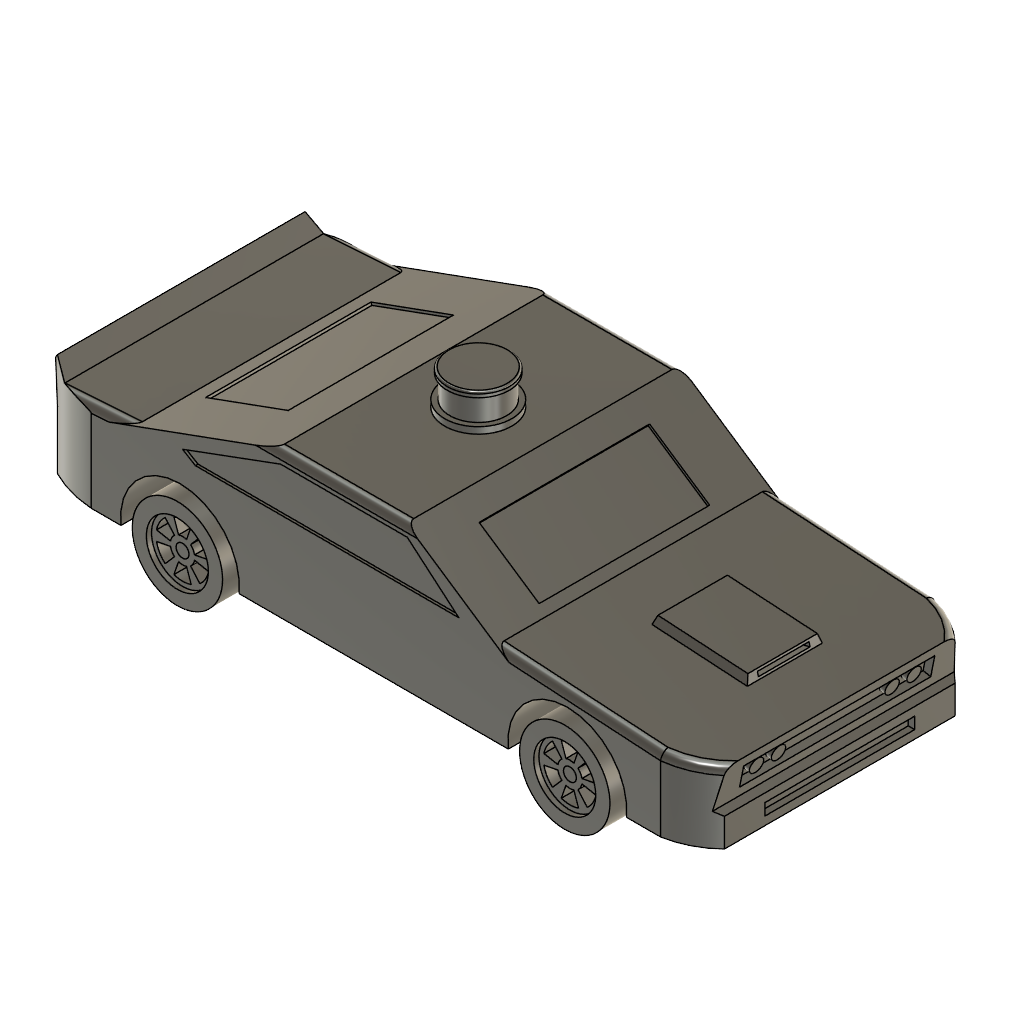
Ackermann_Challenger (Autodesk Fusion 360 design; units mm, degrees)
part number: 2026-11-21-11-42-55-945
part number: 2026-11-21-13-18-45-082
part number: 2026-11-21-13-18-45-097
part number: 2026-11-21-13-18-45-101
part number: 2026-11-21-13-18-45-105
part number: 2026-11-21-13-18-45-110
part number: 2026-11-21-13-18-45-114
part number: 2026-11-21-13-18-45-119
part number: 2026-11-21-13-18-45-123
part number: 2026-11-21-13-18-45-128
part number: 2026-11-21-15-02-55-221
part number: 2026-11-21-15-02-55-302
part number: 2026-11-21-15-02-55-381
part number: 2026-11-21-15-02-55-462
part number: 2026-11-21-15-02-55-542
part number: 2026-11-21-15-02-55-624
part number: 2026-11-21-15-02-55-705
part number: 2026-11-21-15-02-55-805
part number: 2026-11-21-15-02-55-884
Autodesk Fusion 360 part; units mm, degrees
sketch "Boceto1" plane through (0, 0, 0) normal (0, 0, 1) x (1, 0, 0)
  line L0 (245, -50) -> (-245, -50)
  line L1 (-245, -50) -> (-245, 50)
  line L2 (-245, 50) -> (245, 50)
  line L3 (245, 50) -> (245, -50)
  line L4 (245, -50) -> (-245, 50) construction
  line L5 (-245, -50) -> (245, 50) construction
  line L6 (0, 0) -> (150, 0) construction
  line L7 (163, -60) -> (137, -60)
  line L8 (137, -60) -> (137, 60)
  line L9 (137, 60) -> (163, 60)
  line L10 (163, 60) -> (163, -60)
  line L11 (163, -60) -> (137, 60) construction
  line L12 (137, -60) -> (163, 60) construction
  line L13 (0, 0) -> (-150, 0) construction
  line L14 (-137, 60) -> (-163, 60)
  line L15 (-163, 60) -> (-163, -60)
  line L16 (-163, -60) -> (-137, -60)
  line L17 (-137, -60) -> (-137, 60)
  line L18 (-137, 60) -> (-163, -60) construction
  line L19 (-163, 60) -> (-137, -60) construction
  circle A0 centre (150, -60) radius 4
  circle A1 centre (150, 60) radius 4
  line L20 (137, 68) -> (163, 68)
  line L21 (163, 68) -> (163, -68)
  line L22 (163, -68) -> (137, -68)
  line L23 (137, -68) -> (137, 68)
  line L24 (137, 68) -> (163, -68) construction
  line L25 (163, 68) -> (137, -68) construction
  point P0 (150, 0)
  point P1 (-150, 0)
  point P2 (150, 0)
  dimension "d1" = 490
  dimension "d2" = 100
  dimension "d3" = 150
  dimension "d4" = 26
  dimension "d5" = 120
  dimension "d6" = 150
  dimension "d7" = 26
  dimension "d8" = 120
  dimension "d13" = 8
  dimension "d14" = 8
  dimension "d23" = 10
  dimension "d24" = 10
  dimension "d25" = 136
  constraint horizontal L0
  constraint perpendicular L0 L1
  constraint parallel L0 L2
  constraint parallel L1 L3
  constraint coincident L4 L6.start
  constraint coincident L5 L6.start
  constraint coincident L6.start L13.start
  constraint horizontal L6
  constraint horizontal L7
  constraint perpendicular L7 L8
  constraint parallel L7 L9
  constraint parallel L8 L10
  constraint coincident L11 P2
  constraint coincident L12 P2
  constraint coincident P2 P0
  constraint parallel L6 L13
  constraint horizontal L14
  constraint perpendicular L14 L15
  constraint parallel L14 L16
  constraint parallel L15 L17
  constraint coincident L18 P1
  constraint coincident L19 P1
  constraint coincident P1 L13.end
  constraint midpoint L7 A0.centre
  constraint midpoint L9 A1.centre
  constraint horizontal L20
  constraint perpendicular L20 L21
  constraint parallel L20 L22
  constraint parallel L21 L23
  constraint coincident L24 P2
  constraint coincident L25 P2
  measures "d1" distance of L1.end L2.end
  measures "d2" distance of L0.end L1.end
  measures "d3" distance of L6.start P2
  measures "d4" distance of L8.end L9.end
  measures "d5" distance of L7.end L8.end
  measures "d6" distance of L6.start P1
  measures "d7" distance of L15.end L16.end
  measures "d8" distance of L14.end L15.end
  measures "d13" diameter of A0
  measures "d14" diameter of A1
  measures "d23" distance of L0 A0.centre
  measures "d24" distance of L2 A1.centre
  measures "d25" distance of L20.end L21.end
extrude "Extruir1" add sketch "Boceto1" along normal blind 10 contours L0 L2 L3 L10 L21 | L0 L7 L8 L10 A0 L21 L23 | L0 L2 L8 L10 L21 L23 | L0 L2 L8 L17 L23 | L2 L8 L9 L10 A1 L21 L23 | L7 A0 L21 L22 L23 | L0 L15 L16 L17 | L0 L2 L15 L17 | L9 A1 L20 L21 L23 | L0 L1 L2 L15 | L2 L14 L15 L17 makes body 1
sketch "Boceto2" plane through (0, -60, 0) normal (0, -1, 0) x (1, 0, 0)
  line L0 (-163, 0) -> (-137, 0)
  line L1 (-137, 0) -> (-137, 10)
  line L2 (-137, 10) -> (-163, 10)
  line L3 (-163, 10) -> (-163, 0)
  line L4 (0, 10) -> (-150, 10) construction
  line L5 (-150, 10) -> (-150, 5) construction
  circle A0 centre (-150, 5) radius 5
  dimension "d17" = 150
  dimension "d18" = 10
  constraint perpendicular L1 L4
  constraint perpendicular L4 L5
  constraint coincident L5.end A0.centre
  measures "d17" distance of L4.start L4.end
  measures "d18" diameter of A0
extrude "Extruir2" add sketch "Boceto2" along normal blind 25 contours A0 bodies 1
mirror "Simetría1" about plane through (0, 0, 0) normal (0, 1, 0) of "Extruir2"
extrude "Extruir3" add sketch "Boceto1" along normal blind 16 from surface at -3 separate body contours L7 A0 | L7 A0 | L9 A1 | L9 A1 makes body 2 at (153.1885, -57.5848, 2.3333) makes body 3 at (147.2071, 57.1365, 7.6667)
ref_plane "PlanoDeObra1" through (0, 0, 10.5) normal (0, 0, 1) x (1, 0, 0)
sketch "Boceto3" plane through (0, 0, 10.5) normal (0, 0, 1) x (1, 0, 0)
  line L0 (144, 54) -> (156, 54)
  line L1 (156, 54) -> (156, 81)
  line L2 (156, 81) -> (144, 81)
  line L3 (144, 81) -> (144, 54)
extrude "Extruir4" add sketch "Boceto3" along normal blind 4 bodies 3
ref_plane "PlanoDeObra2" through (0, 0, -0.5) normal (0, 0, 1) x (1, 0, 0)
sketch "Boceto4" plane through (0, 0, -0.5) normal (0, 0, 1) x (1, 0, 0)
  line L0 (144, 54) -> (156, 54)
  line L1 (156, 54) -> (156, 81)
  line L2 (156, 81) -> (144, 81)
  line L3 (144, 81) -> (144, 54)
extrude "Extruir5" add sketch "Boceto4" against normal blind 4 bodies 3
sketch "Boceto5" plane through (0, 0, -0.5) normal (0, 0, 1) x (1, 0, 0)
  line L0 (144, 76) -> (156, 76)
  line L1 (156, 76) -> (156, 81)
  line L2 (156, 81) -> (144, 81)
  line L3 (144, 81) -> (144, 76)
extrude "Extruir6" add sketch "Boceto5" along normal blind 11 bodies 3
ref_plane "PlanoDeObra3" through (0, 0, 10.5) normal (0, 0, 1) x (1, 0, 0)
sketch "Boceto7" plane through (0, 0, 10.5) normal (0, 0, 1) x (1, 0, 0)
  line L0 (144, -54) -> (156, -54)
  line L1 (156, -54) -> (156, -81)
  line L2 (156, -81) -> (144, -81)
  line L3 (144, -81) -> (144, -54)
extrude "Extruir8" add sketch "Boceto7" along normal blind 4 bodies 2
ref_plane "PlanoDeObra4" through (0, 0, -0.5) normal (0, 0, 1) x (1, 0, 0)
sketch "Boceto8" plane through (0, 0, -0.5) normal (0, 0, 1) x (1, 0, 0)
  line L0 (144, -54) -> (156, -54)
  line L1 (156, -54) -> (156, -81)
  line L2 (156, -81) -> (144, -81)
  line L3 (144, -81) -> (144, -54)
extrude "Extruir9" add sketch "Boceto8" against normal blind 4 bodies 2
sketch "Boceto9" plane through (0, 0, -0.5) normal (0, 0, 1) x (1, 0, 0)
  line L0 (144, -76) -> (156, -76)
  line L1 (156, -76) -> (156, -81)
  line L2 (156, -81) -> (144, -81)
  line L3 (144, -81) -> (144, -76)
extrude "Extruir10" add sketch "Boceto9" along normal blind 11 bodies 2
sketch "Boceto11" plane through (0, 81, 0) normal (0, 1, 0) x (1, 0, 0)
  line L0 (156, -14.5) -> (156, 4.5)
  line L1 (156, 4.5) -> (144, 4.5)
  line L2 (144, 4.5) -> (144, -14.5)
  line L3 (144, -14.5) -> (156, -14.5)
  circle A0 centre (150, -5) radius 5
extrude "Extruir12" add sketch "Boceto11" along normal blind 22 contours A0 bodies 3
sketch "Boceto12" plane through (0, -81, 0) normal (0, -1, 0) x (-1, 0, 0)
  line L0 (-144, -14.5) -> (-144, 4.5)
  line L1 (-144, 4.5) -> (-156, 4.5)
  line L2 (-156, 4.5) -> (-156, -14.5)
  line L3 (-156, -14.5) -> (-144, -14.5)
  circle A0 centre (-150, -5) radius 5
extrude "Extruir13" add sketch "Boceto12" along normal blind 22 contours A0 bodies 2
extrude "Extruir14" add 1 faces at (-148.7042, -85, 3.3751) along direction (0, -1, 0) blind 18 on bodies 1 bodies 1
extrude "Extruir15" add 1 faces at (-149.3911, 85, 2.9517) along direction (0, 1, 0) blind 18 on bodies 1 bodies 1
sketch "Boceto13" plane through (0, -103, 0) normal (0, -1, 0) x (1, 0, 0)
  circle A0 centre (150, 5) radius 5
  circle A1 centre (150, 5) radius 35
  circle A2 centre (150, 5) radius 24
  circle A3 centre (150, 5) radius 5
  dimension "d61" = 70
  dimension "d62" = 48
  dimension "d63" = 10
  constraint concentric A0 A1
  constraint concentric A1 A2
  constraint concentric A2 A3
  measures "d61" diameter of A1
  measures "d62" diameter of A2
  measures "d63" diameter of A3
extrude "Extruir17" add sketch "Boceto13" along normal blind 5 and the other way blind 21 separate body contours A1 makes body 4
extrude "Extruir18" add sketch "Boceto13" along normal blind 1 and the other way blind 17 separate body contours A2 makes body 5
combine "Combinar1" operation add target body 4 tool bodies 5
sketch "Boceto14" plane through (0, -104, 0) normal (0, -1, 0) x (1, 0, 0)
  circle A0 centre (150, 5) radius 5
  circle A1 centre (150, 5) radius 24
  arc A2 (153.0929, 13.9824) -> (146.9071, 13.9824) centre (150, 5) ccw
  arc A3 (156.6741, 24.3831) -> (143.3259, 24.3831) centre (150, 5) ccw
  line L0 (153.0929, 13.9824) -> (156.6741, 24.3831)
  line L1 (146.9071, 13.9824) -> (143.3259, 24.3831)
  arc A4 (143.7674, 12.1697) -> (140.6745, 6.8127) centre (150, 5) ccw
  arc A5 (136.5508, 20.4715) -> (129.8766, 8.9116) centre (150, 5) ccw
  line L2 (143.7674, 12.1697) -> (136.5508, 20.4715)
  line L3 (140.6745, 6.8127) -> (129.8766, 8.9116)
  arc A6 (140.6745, 3.1873) -> (143.7674, -2.1697) centre (150, 5) ccw
  arc A7 (129.8766, 1.0884) -> (136.5508, -10.4715) centre (150, 5) ccw
  line L4 (140.6745, 3.1873) -> (129.8766, 1.0884)
  line L5 (143.7674, -2.1697) -> (136.5508, -10.4715)
  arc A8 (146.9071, -3.9824) -> (153.0929, -3.9824) centre (150, 5) ccw
  arc A9 (143.3259, -14.3831) -> (156.6741, -14.3831) centre (150, 5) ccw
  line L6 (146.9071, -3.9824) -> (143.3259, -14.3831)
  line L7 (153.0929, -3.9824) -> (156.6741, -14.3831)
  arc A10 (156.2326, -2.1697) -> (159.3255, 3.1873) centre (150, 5) ccw
  arc A11 (163.4492, -10.4715) -> (170.1234, 1.0884) centre (150, 5) ccw
  line L8 (156.2326, -2.1697) -> (163.4492, -10.4715)
  line L9 (159.3255, 3.1873) -> (170.1234, 1.0884)
  arc A12 (159.3255, 6.8127) -> (156.2326, 12.1697) centre (150, 5) ccw
  arc A13 (170.1234, 8.9116) -> (163.4492, 20.4715) centre (150, 5) ccw
  line L10 (159.3255, 6.8127) -> (170.1234, 8.9116)
  line L11 (156.2326, 12.1697) -> (163.4492, 20.4715)
extrude "Extruir19" cut sketch "Boceto14" against normal blind 18 contours A2 A3 L0 L1 | A4 A5 L2 L3 | A6 A7 L4 L5 | A8 A9 L6 L7 | A10 A11 L8 L9 | A12 A13 L10 L11 bodies 4
mirror "Simetría2" about plane through (0, 0, 0) normal (0, 1, 0) of bodies 4 makes body 6
mirror "Simetría3" about plane through (0, 0, 0) normal (1, 0, 0) of bodies 6 4 makes body 7 at (-184.9565, -89, 3.2554) makes body 8 at (-184.9565, 89, 3.2554)
sketch "Boceto15" plane through (0, 0, 0) normal (0, 1, 0) x (1, 0, 0)
  line L0 (-255, 0) -> (255, 0)
  line L1 (255, 0) -> (255, -22)
  line L2 (255, -22) -> (250, -25)
  line L3 (250, -25) -> (256, -55)
  line L4 (256, -55) -> (95, -65)
  line L5 (95, -65) -> (25, -112)
  line L6 (25, -112) -> (-75, -112)
  line L7 (-75, -112) -> (-185, -72)
  line L8 (-185, -72) -> (-245, -68)
  line L9 (-245, -68) -> (-255, -80)
  line L10 (-255, -80) -> (-258, -76)
  line L11 (-258, -76) -> (-255, -45)
  line L12 (-255, -45) -> (-255, 0)
extrude "Extruir20" add sketch "Boceto15" along normal mid plane 212 separate body makes body 9
sketch "Boceto16" plane through (0, -106, 0) normal (0, -1, 0) x (1, 0, 0)
  line L0 (-258, 76) -> (-255, 45)
  line L1 (-255, 45) -> (-255, 0)
  line L2 (-255, 0) -> (255, 0)
  line L3 (255, 0) -> (255, 22)
  line L4 (255, 22) -> (250, 25)
  line L5 (250, 25) -> (256, 55)
  line L6 (256, 55) -> (95, 65)
  line L7 (95, 65) -> (25, 112)
  line L8 (25, 112) -> (-75, 112)
  line L9 (-75, 112) -> (-185, 72)
  line L10 (-185, 72) -> (-245, 68)
  line L11 (-245, 68) -> (-255, 80)
  line L12 (-255, 80) -> (-258, 76)
  line L13 (0, 0) -> (150, 0) construction
  line L14 (0, 0) -> (-150, 0) construction
  line L15 (-150, 0) -> (-150, 5) construction
  line L16 (150, 0) -> (150, 5) construction
  circle A0 centre (150, 5) radius 46
  circle A1 centre (-150, 5) radius 46
  dimension "d84" = 5
  dimension "d85" = 92
  dimension "d86" = 92
  constraint coincident L13.start L14.start
  constraint coincident L2 L13.end
  constraint coincident L2 L14.end
  constraint perpendicular L14 L15
  constraint perpendicular L13 L16
  constraint coincident L16.end A0.centre
  constraint coincident L15.end A1.centre
  measures "d84" distance of L14.end L15.end
  measures "d85" diameter of A0
  measures "d86" diameter of A1
extrude "Extruir21" cut sketch "Boceto16" against normal blind 60 contours L2 A0 | L2 A0 bodies 9
extrude "Extruir22" cut sketch "Boceto16" against normal blind 60 contours L2 A1 | L2 A1 bodies 9
mirror "Simetría4" about plane through (0, 0, 0) normal (0, 1, 0) of "Extruir21", "Extruir22"
sketch "Boceto17" plane through (0, 0, 0) normal (0, 0, -1) x (1, 0, 0)
  circle A0 centre (150, -60) radius 4
  circle A1 centre (150, 60) radius 4
  line L0 (-137, -60) -> (-137, -50)
  line L1 (-137, -50) -> (137, -50)
  line L2 (137, -50) -> (137, -68)
  line L3 (137, -68) -> (163, -68)
  line L4 (163, -68) -> (163, -50)
  line L5 (163, -50) -> (245, -50)
  line L6 (245, -50) -> (245, 50)
  line L7 (245, 50) -> (163, 50)
  line L8 (163, 50) -> (163, 68)
  line L9 (163, 68) -> (137, 68)
  line L10 (137, 68) -> (137, 50)
  line L11 (137, 50) -> (-137, 50)
  line L12 (-137, 50) -> (-137, 60)
  line L13 (-137, 60) -> (-150, 60)
  line L14 (-150, 60) -> (-163, 60)
  line L15 (-163, 60) -> (-163, 50)
  line L16 (-163, 50) -> (-245, 50)
  line L17 (-245, 50) -> (-245, -50)
  line L18 (-245, -50) -> (-163, -50)
  line L19 (-163, -50) -> (-163, -60)
  line L20 (-163, -60) -> (-150, -60)
  line L21 (-150, -60) -> (-137, -60)
  line L22 (241.4001, 51) -> (-250.5999, 51)
  line L23 (-250.5999, 51) -> (-250.5999, -51)
  line L24 (-250.5999, -51) -> (241.4001, -51)
  line L25 (241.4001, -51) -> (241.4001, 51)
  line L26 (241.4001, 51) -> (-250.5999, -51) construction
  line L27 (-250.5999, 51) -> (241.4001, -51) construction
  point P0 (-4.5999, 0)
  dimension "d93" = 492
  dimension "d94" = 102
  constraint horizontal L22
  constraint perpendicular L22 L23
  constraint parallel L22 L24
  constraint parallel L23 L25
  constraint coincident L26 P0
  constraint coincident L27 P0
  measures "d93" distance of L23.end L24.end
  measures "d94" distance of L22.end L23.end
extrude "Extruir23" cut sketch "Boceto17" against normal blind 12 contours L0 L1 L2 L4 L5 L7 L8 L10 L11 L12 L15 L16 L17 L18 L19 L22 L24 L25 bodies 9
combine "Combinar2" operation cut target body 9 tool bodies 1 keep tools
sketch "Boceto18" plane through (0, 0, 0) normal (0, 0, 1) x (1, 0, 0)
  arc A0 (260, 84) -> (200, 106) centre (211.0989, 43.4515) ccw
  line L0 (260, 84) -> (260, 108)
  line L1 (260, 108) -> (200, 108)
  line L2 (200, 108) -> (200, 106)
  arc A1 (200, -106) -> (260, -84) centre (211.0989, -43.4515) ccw
  line L3 (260, -84) -> (260, -108)
  line L4 (260, -108) -> (200, -108)
  line L5 (200, -108) -> (200, -106)
  arc A2 (-205, 106) -> (-262, 92) centre (-211.8588, 10.8893) ccw
  line L6 (-262, 92) -> (-262, 108)
  line L7 (-262, 108) -> (-205, 108)
  line L8 (-205, 108) -> (-205, 106)
  arc A3 (-262, -92) -> (-205, -106) centre (-211.8588, -10.8893) ccw
  line L9 (-262, -92) -> (-262, -108)
  line L10 (-262, -108) -> (-205, -108)
  line L11 (-205, -108) -> (-205, -106)
extrude "Extruir24" cut sketch "Boceto18" along normal blind 120 bodies 9
fillet "Empalme1" radius 6 6 edges at (240.4508, -99.7894, 55.9658) (240.4508, 99.7894, 55.9658) (-201.8588, 106, 70.8761) (158.5989, 106, 61.0498) (158.5989, -106, 61.0498) (-201.8588, -106, 70.8761) on bodies 9
fillet "Empalme2" radius 6 2 edges at (-25, 106, 112) (-25, -106, 112) on bodies 9
sketch "Boceto19" plane through (235.5769, 0, -47.1154) normal (0.980581, 0, -0.196116) x (-0.196116, 0, -0.980581)
  spline S0 degree 3 poles (-104.1377, 79.8705) (-104.1377, 81.6505) (-103.8169, 83.3913) (-102.7018, 86.0852) (-102.0562, 87.0755) (-100.8773, 88.2657) (-100.4028, 88.6396) (-99.3987, 89.2002) (-98.882, 89.3961) (-98.3409, 89.497) knots 0 0 0 0 0.533991 0.533991 0.943783 0.943783 1.172359 1.172359 1.382762 1.382762 1.382762 1.382762
  line L0 (-104.1377, 79.8705) -> (-104.1377, -79.8705)
  spline S1 degree 3 poles (-98.3409, -89.497) (-98.9576, -89.382) (-99.5418, -89.1438) (-100.7644, -88.3955) (-101.361, -87.8358) (-102.522, -86.3715) (-103.065, -85.3559) (-103.9217, -82.8119) (-104.1377, -81.3303) (-104.1377, -79.8705) knots 0 0 0 0 0.18821 0.18821 0.429144 0.429144 0.745547 0.745547 1.120585 1.120585 1.120585 1.120585
  ellipse E0 centre (124.814, -43.4515) end of major axis (448.7323, -43.4515) minor radius 63.5256 (-98.3409, -89.497) -> (-73.5436, -93.673) ccw
  line L1 (-73.5436, -93.673) -> (-73.5436, 93.673)
  ellipse E1 centre (124.814, 43.4515) end of major axis (-199.1042, 43.4515) minor radius 63.5256 (-73.5436, 93.673) -> (-98.3409, 89.497) ccw
  line L2 (-80.8406, -74) -> (-80.8406, 74)
  line L3 (-80.8406, 74) -> (-96.8406, 74)
  line L4 (-96.8406, 74) -> (-96.8406, -74)
  line L5 (-96.8406, -74) -> (-80.8406, -74)
extrude "Extruir25" cut sketch "Boceto19" against normal blind 6 contours L2 L3 L4 L5 bodies 9
sketch "Boceto20" plane through (255, 0, 0) normal (1, 0, 0) x (0, 0, -1)
  line L0 (-22, -89.3666) -> (0, -89.3666)
  line L1 (0, -89.3666) -> (0, 89.3666)
  line L2 (0, 89.3666) -> (-22, 89.3666)
  line L3 (-22, 89.3666) -> (-22, -89.3666)
  line L4 (-6.5, -58) -> (-6.5, 58)
  line L5 (-6.5, 58) -> (-15.5, 58)
  line L6 (-15.5, 58) -> (-15.5, -58)
  line L7 (-15.5, -58) -> (-6.5, -58)
extrude "Extruir26" cut sketch "Boceto20" against normal blind 5 contours L4 L5 L6 L7 bodies 9
sketch "Boceto21" plane through (4.3868, 0, 70.6281) normal (0.061992, 0, 0.998077) x (0.998077, 0, -0.061992)
  line L0 (218.0609, 100) -> (90.7878, 100)
  line L1 (90.7878, 100) -> (90.7878, -100)
  line L2 (90.7878, -100) -> (218.0782, -100)
  ellipse E0 centre (207.4831, -43.4515) end of major axis (265.1195, -43.4515) minor radius 57.5256 (218.0693, -99.9984) -> (252.098, -79.8705) ccw
  line L3 (252.098, -79.8705) -> (252.098, 79.8705)
  ellipse E1 centre (207.4831, 43.4515) end of major axis (265.1195, 43.4515) minor radius 57.5256 (252.098, 79.8705) -> (218.0609, 100) ccw
  line L4 (134.4429, -29) -> (134.4429, 29)
  line L5 (134.4429, 29) -> (208.4429, 29)
  line L6 (208.4429, 29) -> (208.4429, -29)
  line L7 (208.4429, -29) -> (134.4429, -29)
extrude "Extruir27" add sketch "Boceto21" along normal blind 6.5 draft -18 contours L4 L5 L6 L7 bodies 9
sketch "Boceto22" plane through (59.6012, 0, 88.7678) normal (0.557434, 0, 0.830221) x (0.830221, 0, -0.557434)
  ellipse E0 centre (-30.9135, -100) end of major axis (-41.6771, -100) minor radius 6 (-41.6771, -100) -> (-30.9135, -106) ccw
  line L0 (-30.9135, -106) -> (54.5215, -106)
  ellipse E1 centre (54.5215, -100) end of major axis (42.6378, -100) minor radius 6 (42.6378, -100) -> (54.5215, -106) ccw
  line L1 (42.6378, -100) -> (42.6378, 100)
  ellipse E2 centre (54.5215, 100) end of major axis (42.6378, 100) minor radius 6 (54.5215, 106) -> (42.6378, 100) ccw
  line L2 (54.5215, 106) -> (-30.9135, 106)
  ellipse E3 centre (-30.9135, 100) end of major axis (-41.6771, 100) minor radius 6 (-30.9135, 106) -> (-41.6771, 100) ccw
  line L3 (-41.6771, 100) -> (-41.6771, -100)
  line L4 (34.4222, -66) -> (34.4222, 66)
  line L5 (34.4222, 66) -> (-21.5778, 66)
  line L6 (-21.5778, 66) -> (-21.5778, -66)
  line L7 (-21.5778, -66) -> (34.4222, -66)
extrude "Extruir28" cut sketch "Boceto22" against normal blind 2 contours L4 L5 L6 L7 bodies 9
sketch "Boceto23" plane through (-44.7299, 0, 123.0073) normal (-0.341743, 0, 0.939793) x (0.939793, 0, 0.341743)
  ellipse E0 centre (-49.7663, -100) end of major axis (-32.2093, -100) minor radius 6 (-49.7663, -106) -> (-32.2093, -100) ccw
  line L0 (-32.2093, -100) -> (-32.2093, 100)
  ellipse E1 centre (-49.7663, 100) end of major axis (-32.2093, 100) minor radius 6 (-32.2093, 100) -> (-49.7663, 106) ccw
  line L1 (-49.7663, 106) -> (-170.8024, 106)
  ellipse E2 centre (-170.8024, 100) end of major axis (-149.2563, 100) minor radius 6 (-149.2563, 100) -> (-170.8024, 106) ccw
  line L2 (-149.2563, 100) -> (-149.2563, -100)
  ellipse E3 centre (-170.8024, -100) end of major axis (-149.2563, -100) minor radius 6 (-170.8024, -106) -> (-149.2563, -100) ccw
  line L3 (-170.8024, -106) -> (-49.7663, -106)
  line L4 (-67.5059, -64) -> (-67.5059, 64)
  line L5 (-67.5059, 64) -> (-135.5059, 64)
  line L6 (-135.5059, 64) -> (-135.5059, -64)
  line L7 (-135.5059, -64) -> (-67.5059, -64)
extrude "Extruir29" cut sketch "Boceto23" against normal blind 2 contours L4 L5 L6 L7 bodies 9
sketch "Boceto24" plane through (-248.3196, 0, -24.0309) normal (-0.99535, 0, -0.096324) x (-0.096324, 0, 0.99535)
  ellipse E0 centre (-378.5218, 10.8893) end of major axis (-1368.4878, 10.8893) minor radius 95.3577 (100.4982, 94.3403) -> (69.3534, 95.93) ccw
  line L0 (69.3534, 95.93) -> (69.3534, -95.93)
  ellipse E1 centre (-378.5218, -10.8893) end of major axis (611.4441, -10.8893) minor radius 95.3577 (69.3534, -95.93) -> (100.4982, -94.3403) ccw
  line L1 (100.4982, -94.3403) -> (100.4982, 94.3403)
  line L2 (78.4258, -77) -> (78.4258, 77)
  line L3 (78.4258, 77) -> (91.4258, 77)
  line L4 (91.4258, 77) -> (91.4258, -77)
  line L5 (91.4258, -77) -> (78.4258, -77)
extrude "Extruir30" cut sketch "Boceto24" against normal blind 4 contours L2 L3 L4 L5 bodies 9
sketch "Boceto25" plane through (0, 0, 112) normal (0, 0, 1) x (1, 0, 0)
  line L0 (-75, -100) -> (25, -100)
  line L1 (25, -100) -> (25, 100)
  line L2 (25, 100) -> (-75, 100)
  line L3 (-75, 100) -> (-75, -100)
  circle A0 centre (-25, 0) radius 26
extrude "Extruir31" add sketch "Boceto25" along normal blind 5 separate body contours A0 makes body 10
sketch "Boceto26" plane through (0, 0, 117) normal (0, 0, 1) x (1, 0, 0)
  circle A0 centre (-25, 0) radius 26
  circle A1 centre (-25, 0) radius 22
extrude "Extruir32" add sketch "Boceto26" along normal blind 18 bodies 10
sketch "Boceto27" plane through (0, 0, 135) normal (0, 0, 1) x (1, 0, 0)
  circle A0 centre (-25, 0) radius 22
  circle A1 centre (-25, 0) radius 26
  circle A2 centre (-25, 0) radius 24
extrude "Extruir33" add sketch "Boceto27" along normal blind 4 contours A2 bodies 10
sketch "Boceto28" plane through (229.6934, 0, -45.9387) normal (0.980581, 0, -0.196116) x (-0.196116, 0, -0.980581)
  line L0 (-96.8406, -74) -> (-80.8406, -74)
  line L1 (-80.8406, -74) -> (-80.8406, 74)
  line L2 (-80.8406, 74) -> (-96.8406, 74)
  line L3 (-96.8406, 74) -> (-96.8406, -74)
  circle A0 centre (-88.8406, -61) radius 5.5
  circle A1 centre (-88.8406, -44) radius 5.5
  circle A2 centre (-88.8406, 44) radius 5.5
  circle A3 centre (-88.8406, 61) radius 5.5
extrude "Extruir34" add sketch "Boceto28" along normal blind 4.5 contours A0 | A1 | A2 | A3 bodies 9
sketch "Boceto29" plane through (213.1494, 0, 54.9092) normal (0.968384, 0, 0.249464) x (0, 1, 0)
  line L0 (26.888, 9.7229) -> (-26.888, 9.7229)
  line L1 (-26.888, 9.7229) -> (-29, 2.8884)
  line L2 (-29, 2.8884) -> (29, 2.8884)
  line L3 (29, 2.8884) -> (26.888, 9.7229)
  line L4 (-20, 4.7057) -> (20, 4.7057)
  line L5 (20, 4.7057) -> (20, 7.9057)
  line L6 (20, 7.9057) -> (-20, 7.9057)
  line L7 (-20, 7.9057) -> (-20, 4.7057)
extrude "Extruir35" cut sketch "Boceto29" against normal blind 10 contours L4 L5 L6 L7 bodies 9
sketch "Boceto30" plane through (0, 106, 0) normal (0, 1, 0) x (0, 0, 1)
  line L0 (106, -91.5) -> (106, 33.9362)
  line L1 (106, 33.9362) -> (58.3756, 104.8661)
  line L2 (58.3756, 104.8661) -> (51.088, 222.1978)
  line L3 (51.088, 222.1978) -> (0, 222.1978)
  line L4 (0, 222.1978) -> (0, 195.7275)
  arc A0 (0, 104.2725) -> (0, 195.7275) centre (5, 150) ccw
  line L5 (0, 104.2725) -> (0, -104.2725)
  arc A1 (0, -195.7275) -> (0, -104.2725) centre (5, -150) ccw
  line L6 (0, -195.7275) -> (0, -218.7176)
  line L7 (0, -218.7176) -> (63.7388, -218.7176)
  line L8 (63.7388, -218.7176) -> (64.6368, -205.2489)
  line L9 (64.6368, -205.2489) -> (106, -91.5)
  line L10 (69, 66) -> (103, 26)
  line L11 (103, 26) -> (103, -72)
  line L12 (103, -72) -> (75, -148)
  line L13 (75, -148) -> (69, -138)
  line L14 (69, -138) -> (69, 66)
extrude "Extruir36" cut sketch "Boceto30" against normal blind 2 contours L10 L11 L12 L13 L14 bodies 9
sketch "Boceto31" plane through (0, -106, 0) normal (0, -1, 0) x (0, 0, -1)
  line L0 (-106, 33.9362) -> (-106, -91.5)
  line L1 (-106, -91.5) -> (-64.6368, -205.2489)
  line L2 (-64.6368, -205.2489) -> (-63.7388, -218.7176)
  line L3 (-63.7388, -218.7176) -> (0, -218.7176)
  line L4 (0, -218.7176) -> (0, -195.7275)
  arc A0 (0, -104.2725) -> (0, -195.7275) centre (-5, -150) ccw
  line L5 (0, -104.2725) -> (0, 104.2725)
  arc A1 (0, 195.7275) -> (0, 104.2725) centre (-5, 150) ccw
  line L6 (0, 195.7275) -> (0, 222.1978)
  line L7 (0, 222.1978) -> (-51.1531, 222.1978)
  line L8 (-51.0882, 222.1937) -> (-58.3756, 104.8661)
  line L9 (-58.3756, 104.8661) -> (-106, 33.9362)
  line L10 (-69, 66) -> (-103, 26)
  line L11 (-103, 26) -> (-103, -72)
  line L12 (-103, -72) -> (-75, -148)
  line L13 (-75, -148) -> (-69, -138)
  line L14 (-69, -138) -> (-69, 66)
extrude "Extruir37" cut sketch "Boceto31" against normal blind 2 bodies 9
delete_body "QuitarCuerpo1" bodies 10
ref_plane "PlanoDeObra5" through (0, 0, 112) normal (0, 0, 1) x (1, 0, 0)
sketch "Boceto32" plane through (0, 0, 112) normal (0, 0, 1) x (1, 0, 0)
  circle A0 centre (-25, 0) radius 26
extrude "Extruir38" add sketch "Boceto32" along normal blind 5 separate body makes body 11
ref_plane "PlanoDeObra6" through (0, 0, 117) normal (0, 0, 1) x (1, 0, 0)
sketch "Boceto33" plane through (0, 0, 117) normal (0, 0, 1) x (1, 0, 0)
  circle A0 centre (-25, 0) radius 22
extrude "Extruir39" add sketch "Boceto33" along normal blind 18 bodies 11
ref_plane "PlanoDeObra7" through (0, 0, 135) normal (0, 0, 1) x (1, 0, 0)
sketch "Boceto34" plane through (0, 0, 135) normal (0, 0, 1) x (1, 0, 0)
  circle A0 centre (-25, 0) radius 24
extrude "Extruir40" add sketch "Boceto34" along normal blind 4 bodies 11
fillet "Empalme3" radius 1.5 1 edges at (-47.3759, -8.6788, 139) on bodies 11
copy_body "Cuerpo - > Comp.1" bodies 1 removing the originals makes body 12 in component "old_component"
copy_body "Cuerpo - > Comp.2" bodies 2 removing the originals makes body 13 in component "old_component (1)"
copy_body "Cuerpo - > Comp.3" bodies 3 removing the originals makes body 14 in component "old_component (2)"
copy_body "Cuerpo - > Comp.4" bodies 4 removing the originals makes body 15 in component "old_component (3)"
copy_body "Cuerpo - > Comp.5" bodies 6 removing the originals makes body 16 in component "old_component (4)"
copy_body "Cuerpo - > Comp.6" bodies 7 removing the originals makes body 17 in component "old_component (5)"
copy_body "Cuerpo - > Comp.7" bodies 8 removing the originals makes body 18 in component "old_component (6)"
copy_body "Cuerpo - > Comp.8" bodies 9 removing the originals makes body 19 in component "old_component (7)"
copy_body "Cuerpo - > Comp.9" bodies 11 removing the originals makes body 20 in component "old_component (8)"
extrude "Extruir1'" add 1 faces at (-149.3911, 103, 2.9517) along direction (0, 1, 0) blind 1 on bodies 12 bodies 12 in component "old_component"
extrude "Extruir2'" add 1 faces at (-148.7042, -103, 3.3751) along direction (0, -1, 0) blind 1 on bodies 12 bodies 12 in component "old_component"
extrude "Extruir1''" add 1 faces at (149.3911, -103, 6.5515) along direction (0, -1, 0) blind 1 on bodies 13 bodies 13 in component "old_component (1)"
extrude "Extruir1'''" add 1 faces at (150.6089, 103, 6.5515) along direction (0, 1, 0) blind 1 on bodies 14 bodies 14 in component "old_component (2)"
copy_body "CopiarPegarCuerpos1" bodies 13 body 13 seen with x (1, 0, 0) y (0, 1, 0) z (0, 0, 1) at (0, 0, 30) makes body 21 in component "front_right_steering_link_1"
copy_body "CopiarPegarCuerpos1'" bodies 14 body 14 seen with x (1, 0, 0) y (0, 1, 0) z (0, 0, 1) at (0, 0, 30) makes body 22 in component "front_left_steering_link_1"
copy_body "CopiarPegarCuerpos1''" bodies 15 body 15 seen with x (1, 0, 0) y (0, 1, 0) z (0, 0, 1) at (0, 0, 30) makes body 23 in component "front_right_wheel_link_1"
copy_body "CopiarPegarCuerpos1'''" bodies 16 body 16 seen with x (1, 0, 0) y (0, 1, 0) z (0, 0, 1) at (0, 0, 30) makes body 24 in component "front_left_wheel_link_1"
copy_body "CopiarPegarCuerpos1''''" bodies 17 body 17 seen with x (1, 0, 0) y (0, 1, 0) z (0, 0, 1) at (0, 0, 30) makes body 25 in component "rear_right_wheel_link_1"
copy_body "CopiarPegarCuerpos1'''''" bodies 18 body 18 seen with x (1, 0, 0) y (0, 1, 0) z (0, 0, 1) at (0, 0, 30) makes body 26 in component "rear_left_wheel_link_1"
copy_body "CopiarPegarCuerpos1''''''" bodies 19 body 19 seen with x (1, 0, 0) y (0, 1, 0) z (0, 0, 1) at (0, 0, 30) makes body 27 in component "chassis_body_link_1"
copy_body "CopiarPegarCuerpos1'''''''" bodies 20 body 20 seen with x (1, 0, 0) y (0, 1, 0) z (0, 0, 1) at (0, 0, 30) makes body 28 in component "lidar_link_1"
copy_body "CopiarPegarCuerpos1''''''''" bodies 12 body 12 seen with x (1, 0, 0) y (0, 1, 0) z (0, 0, 1) at (0, 0, 30) makes body 29 in component "base_link"
component "old_component (1)" placed x (1, 0, 0) y (0, 1, 0) z (0, 0, 1) at (0, 0, 30)
component "old_component (2)" placed x (1, 0, 0) y (0, 1, 0) z (0, 0, 1) at (0, 0, 30)
component "old_component (3)" placed x (1, 0, 0) y (0, 1, 0) z (0, 0, 1) at (0, 0, 30)
component "old_component (4)" placed x (1, 0, 0) y (0, 1, 0) z (0, 0, 1) at (0, 0, 30)
component "old_component (5)" placed x (1, 0, 0) y (0, 1, 0) z (0, 0, 1) at (0, 0, 30)
component "old_component (6)" placed x (1, 0, 0) y (0, 1, 0) z (0, 0, 1) at (0, 0, 30)
component "old_component (7)" placed x (1, 0, 0) y (0, 1, 0) z (0, 0, 1) at (0, 0, 30)
component "old_component (8)" placed x (1, 0, 0) y (0, 1, 0) z (0, 0, 1) at (0, 0, 30)
component "old_component" placed x (1, 0, 0) y (0, 1, 0) z (0, 0, 1) at (0, 0, 30)
component "front_right_steering_link_1" placed x (1, 0, 0) y (0, 1, 0) z (0, 0, 1) at (0, 0, 0)
component "front_left_steering_link_1" placed x (1, 0, 0) y (0, 1, 0) z (0, 0, 1) at (0, 0, 0)
component "front_right_wheel_link_1" placed x (1, 0, 0) y (0, 1, 0) z (0, 0, 1) at (0, 0, 0)
component "front_left_wheel_link_1" placed x (1, 0, 0) y (0, 1, 0) z (0, 0, 1) at (0, 0, 0)
component "rear_right_wheel_link_1" placed x (1, 0, 0) y (0, 1, 0) z (0, 0, 1) at (0, 0, 0)
component "rear_left_wheel_link_1" placed x (1, 0, 0) y (0, 1, 0) z (0, 0, 1) at (0, 0, 0)
component "chassis_body_link_1" placed x (1, 0, 0) y (0, 1, 0) z (0, 0, 1) at (0, 0, 0)
component "lidar_link_1" placed x (1, 0, 0) y (0, 1, 0) z (0, 0, 1) at (0, 0, 0)
component "base_link" placed x (1, 0, 0) y (0, 1, 0) z (0, 0, 1) at (0, 0, 0)
named bodies: "Mangueta_Derecha", "Mangueta_Izquierda", "LiDAR_360", "Chasis_Base", "Rueda_Delantera_Derecha", "Rueda_Delantera_Izquierda", "Rueda_Trasera_Derecha", "Rueda_Trasera_Izquierda", "Carroceria_Challenger"
